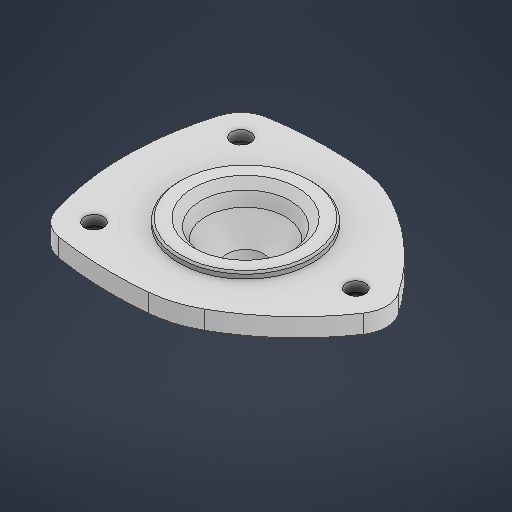
# Autodesk Inventor part: sensormout_pendulum
Saved by Autodesk Inventor 2027.1 (Build 311270010, 270A)
## iProperties
Created: 2026-10-10
Part Number: sensormout_pendulum
Material: Generic
Document SubType Name: Modeling
Designer: lucao
Density: 0.648332 g/cm^3
Appearance: Default
Mass: 3.49 g
Surface Area: 32.254 cm^2
Volume: 5.38304 cm^3
Author: lucao
## iProperties of the stored document sensormout_pendulum_3DPrint.ipt
Created: 2026-10-17
Part Number: sensormout_pendulum_3DPrint
Material: Generic
Document SubType Name: Modeling
Designer: lucao
Density: 1 g/cm^3
Appearance: Default
Author: lucao
Autodesk Inventor part; units mm, degrees
ref_plane "XZ Plane" through (0, 0, 0) normal (0, 1, 0) x (-1, 0, 0)
ref_plane "XY Plane" through (0, 0, 0) normal (0, 0, 1) x (1, 0, 0)
sketch "Sketch1" plane through (0, 0, 0) normal (0, 1, 0) x (-1, 0, 0)
  circle A0 centre (0, 0) radius 17.5
  circle A1 centre (-18, 0) radius 1.55
  circle A2 centre (-18, 0) radius 5
  arc A3 (-8.528549, 15.28116) -> (-22.137897, 2.806744) centre (10.965278, -19.647205) ccw
  arc A4 (-22.137897, -2.806744) -> (-8.528549, -15.28116) centre (10.965278, 19.647205) ccw
  circle A5 centre (12.737739, 12) radius 1.55
  circle A6 centre (12.737739, -12) radius 1.55
  circle A7 centre (12.737739, -12) radius 5
  circle A8 centre (12.737739, 12) radius 5
  arc A9 (13.528573, 16.937062) -> (-1.662939, 17.42081) centre (4.038565, -42.307682) ccw
  arc A10 (-1.662939, -17.42081) -> (13.528573, -16.937062) centre (4.038565, 42.307682) ccw
  arc A11 (17.507435, -13.5) -> (17.507435, 13.5) centre (-25.419829, 0) ccw
  dimension "d0" = 35
  dimension "d1" = 3.1
  dimension "d2" = 10
  dimension "d3" = 40
  dimension "d4" = 40
  dimension "d5" = 3.1
  dimension "d6" = 3.1
  dimension "d7" = 12
  dimension "d8" = 12
  dimension "d9" = 10
  dimension "d10" = 10
  dimension "d11" = 60
  dimension "d12" = 60
  dimension "d13" = 45
  dimension "d29" = 18
  constraints: 21 point on circle, 12 centre point, 10 tangent, 4 coincident, 1 horizontal alignment, 1 vertical alignment
  measures "d0" diameter of A0
  measures "d1" diameter of A1
  measures "d2" diameter of A2
  measures "d3" radius of A3
  measures "d4" radius of A4
  measures "d5" diameter of A5
  measures "d6" diameter of A6
  measures "d7" vertical distance of point (0, 0) A6.centre
  measures "d8" vertical distance of A5.centre point (0, 0)
  measures "d9" diameter of A7
  measures "d10" diameter of A8
  measures "d11" radius of A10
  measures "d12" radius of A9
  measures "d13" radius of A11
  measures "d29" distance of point (0, 0) A1.centre
extrude "Extrusion1" add sketch "Sketch1" along normal blind 3.5 contours A0 A8 A7 A2 | A9 A8 A0 | A0 A2 A3 | A8 A0 A5 | A0 A5 A8 | A2 A0 A1 | A0 A1 A2 | A8 A11 A7 A0 | A2 A0 A4 | A7 A0 A6 | A0 A6 A7 | A10 A0 A7
sketch "Sketch2" plane through (0, 3.5, 0) normal (0, 1, 0) x (1, 0, 0)
  circle A0 centre (0, 0) radius 6.5
  dimension "d16" = 13
  constraints: 1 centre point, 1 coincident
  measures "d16" diameter of A0
extrude "Extrusion2" cut sketch "Sketch2" against normal blind 4
sketch "Sketch3" plane through (0, 3.5, 0) normal (0, 1, 0) x (1, 0, 0)
  circle A0 centre (0, 0) radius 10.85
  circle A1 centre (0, 0) radius 8.5
  dimension "d19" = 21.7
  dimension "d20" = 17
  constraints: 2 centre point, 2 coincident
  measures "d19" diameter of A0
  measures "d20" diameter of A1
extrude "Extrusion3" add sketch "Sketch3" along normal blind 1
chamfer "Chamfer1" distance 1 angle 45 1 edges at (-8.5, 3.5, 0)
chamfer "Chamfer2" distance 1 angle 45 1 edges at (-6.5, 3.5, 0)
chamfer "Chamfer3" distance 1.9 angle 45 3 edges at (19.55, 0, 0) (-11.1877, 0, 12) (-11.1877, 0, -12)
sketch "Sketch4" plane through (0, 0, 0) normal (0, -1, 0) x (1, 0, 0)
  circle A0 centre (-12.737739, 12) radius 3.45
  arc A1 (22.137897, -2.806744) -> (22.137897, 2.806744) centre (18, 0) ccw
  arc A2 (22.137897, 2.806744) -> (8.528549, 15.28116) centre (-10.965278, -19.647205) ccw
  arc A3 (8.528549, 15.28116) -> (1.662939, 17.42081) centre (0, 0) ccw
  arc A4 (1.662939, 17.42081) -> (-13.528573, 16.937062) centre (-4.038565, -42.307682) ccw
  arc A5 (-13.528573, 16.937062) -> (-17.507435, 13.5) centre (-12.737739, 12) ccw
  arc A6 (-17.507435, 13.5) -> (-17.507435, -13.5) centre (25.419829, 0) ccw
  arc A7 (-17.507435, -13.5) -> (-13.528573, -16.937062) centre (-12.737739, -12) ccw
  arc A8 (-13.528573, -16.937062) -> (1.662939, -17.42081) centre (-4.038565, 42.307682) ccw
  arc A9 (1.662939, -17.42081) -> (8.528549, -15.28116) centre (0, 0) ccw
  arc A10 (8.528549, -15.28116) -> (22.137897, -2.806744) centre (-10.965278, 19.647205) ccw
  circle A11 centre (0, 0) radius 6.5
  circle A12 centre (18, 0) radius 3.45
  circle A13 centre (-12.737739, -12) radius 3.45
extrude "Extrusion4" add sketch "Sketch4" along normal blind 4.6
sketch "Sketch8" plane through (0, -4.6, 0) normal (0, -1, 0) x (1, 0, 0)
  circle A0 centre (0, 0) radius 6.5 projected
  circle A1 centre (0, 0) radius 3
  dimension "d53" = 6
  constraints: 1 centre point, 1 coincident
  measures "d53" diameter of A1
extrude "Extrusion7" add sketch "Sketch8" against normal blind 4
sketch "Sketch9" plane through (0, -4.6, 0) normal (0, -1, 0) x (1, 0, 0)
  circle A0 centre (0, 6) radius 1
  circle A1 centre (0, -6) radius 1
  point P0 (0, 0)
  dimension "d56" = 2
  dimension "d57" = 2
  dimension "d58" = 12
  dimension "d59" = 6
  constraints: 2 centre point, 2 vertical alignment
  measures "d56" diameter of A0
  measures "d57" diameter of A1
  measures "d58" distance of A1.centre A0.centre
  measures "d59" distance of point (0, 0) A0.centre
extrude "Extrusion8" cut sketch "Sketch9" against normal blind 3
chamfer "Chamfer6" distance 1.5 angle 45 1 edges at (-3, -0.6, 0)
sketch "Sketch10" plane through (0, -4.6, 0) normal (0, -1, 0) x (1, 0, 0)
  circle A0 centre (0, -6) radius 1
  circle A1 centre (0, 6) radius 1
  circle A2 centre (0, 0) radius 3
  arc A3 (22.137897, 2.806744) -> (8.528549, 15.28116) centre (-10.965278, -19.647205) ccw
  arc A4 (8.528549, 15.28116) -> (1.662939, 17.42081) centre (0, 0) ccw
  arc A5 (1.662939, 17.42081) -> (-13.528573, 16.937062) centre (-4.038565, -42.307682) ccw
  arc A6 (-13.528573, 16.937062) -> (-17.507435, 13.5) centre (-12.737739, 12) ccw
  arc A7 (-17.507435, 13.5) -> (-17.507435, -13.5) centre (25.419829, 0) ccw
  arc A8 (-17.507435, -13.5) -> (-13.528573, -16.937062) centre (-12.737739, -12) ccw
  arc A9 (-13.528573, -16.937062) -> (1.662939, -17.42081) centre (-4.038565, 42.307682) ccw
  arc A10 (1.662939, -17.42081) -> (8.528549, -15.28116) centre (0, 0) ccw
  arc A11 (8.528549, -15.28116) -> (22.137897, -2.806744) centre (-10.965278, 19.647205) ccw
  arc A12 (22.137897, -2.806744) -> (22.137897, 2.806744) centre (18, 0) ccw
  circle A13 centre (-12.737739, -12) radius 3.45
  circle A14 centre (18, 0) radius 3.45
  circle A15 centre (-12.737739, 12) radius 3.45
  circle A16 centre (0, 0) radius 9
  dimension "d65" = 18
  constraints: 1 centre point, 1 coincident
  measures "d65" diameter of A16
extrude "Extrusion9" cut sketch "Sketch10" against normal blind 4.6 contours A12 A11 A10 A9 A8 A7 A6 A5 A4 A3
chamfer "Chamfer7" distance 4.6 angle 45 1 edges at (-9, 0, 0)
chamfer "Chamfer8" distance 0.5 angle 45 10 edges at (16.0627, 0, -9.8398) (5.2068, 0, -16.7074) (-5.9482, 0, -17.6619) (-16.0063, 0, -15.7838) (-19.5802, 0, 0) (-16.0063, 0, 15.7838) (-5.9482, 0, 17.6619) (5.2068, 0, 16.7074) (16.0627, 0, 9.8398) (23, 0, 0)
chamfer "Chamfer9" distance 0.3 angle 45 1 edges at (-10.85, 4.5, 0)
chamfer "Chamfer10" distance 2 angle 45 1 edges at (-6.5, -0.6, 0)
chamfer "Chamfer11" distance 1.1 angle 45 1 edges at (-6.5, 2.5, 0)
ref_plane "Work Plane1" through (-17, 0, 0) normal (1, 0, 0) x (0, 1, 0)
sketch "Sketch11" plane through (-17, 0, 0) normal (1, 0, 0) x (0, 1, 0)
  line L0 (0, 13.6) -> (0, -13.6)
  arc A0 (0, -3.65) -> (0, 3.65) centre (-1.636307, 0) ccw
  arc A1 (-0.409077, -2.7375) -> (-0.409077, 2.7375) centre (-1.636307, 0) ccw
  point P0 (0, 0)
  point P1 (0, 0)
  point P2 (0, 2.514458)
  point P3 (0, -2.514458)
  dimension "d84" = 7.3
  dimension "d85" = 4
  dimension "d86" = 1
  constraints: 4 point on circle, 2 centre point, 2 point on line, 1 horizontal alignment, 1 midpoint
  measures "d84" distance of A0.start A0.end
  measures "d85" radius of A0
  measures "d86" radial gap between concentric circles of A0 A1
extrude "Extrusion10" cut sketch "Sketch11" along normal mid plane 2 contours A0 L0 A1
fillet "Fillet3" radius 2 2 edges at (-17, 0, 3.65) (-17, 0, -3.65)
fillet "Fillet4" radius 0.3 2 edges at (-17, 0, 2.5145) (-17, 0, -2.5145)
body "Solid1"
